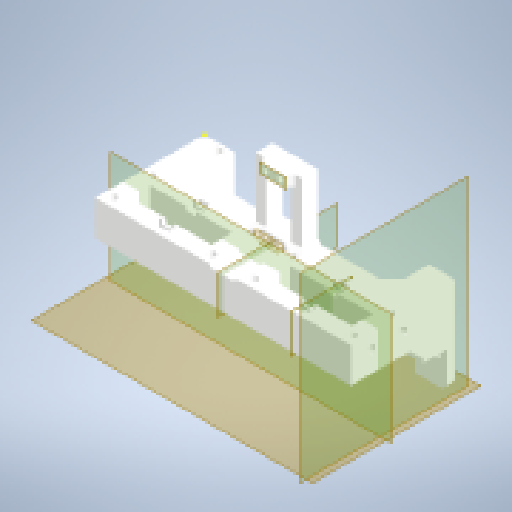
# Autodesk Inventor part: крепление ушей
Saved by Autodesk Inventor 2024.2 (Build 282272000, 272)
## iProperties
Created: 2026-10-17
Part Number: крепление ушей
Material: PLA
Document SubType Name: Modeling
Designer: katya_notebook
Density: 1.24 g/cm^3
Appearance: Типовые
Author: katya_notebook
Autodesk Inventor part; units mm, degrees
ref_plane "РабПлоскость1" through (124, 0, 0) normal (-1, 0, 0) x (0, 0, 1)
sketch "Эскиз1" plane through (124, 0, 0) normal (-1, 0, 0) x (0, 0, 1)
  line L0 (26, 41.5014) -> (53, 41.5014)
  line L1 (53, 41.5014) -> (53, 24.5014)
  line L2 (53, 24.5014) -> (26, 24.5014)
  line L3 (26, 24.5014) -> (26, 41.5014)
  line L4 (4.9014, 14.5719) -> (64.9014, 14.5719) projected
  line L5 (42.1269, 20.5014) -> (32.0731, 20.5014) projected
  point P0 (0, 0)
  dimension "d1" = 27
  dimension "d3" = 17
  dimension "d4" = 4
  dimension "d11" = 26
  constraints: 8 end point, 2 parallel, 1 horizontal, 1 perpendicular
  measures "d1" distance between parallel lines of L3 L1
  measures "d3" distance of L2.end L0.start
  measures "d4" distance between parallel lines of L2 L5
  measures "d11" distance from line of L3 point (0, 0)
ref_plane "РабПлоскость2" through (0, -1.6936, -1.831) normal (1, 0, 0) x (0, 1, 0)
ref_plane "РабПлоскость5" through (0, -2.5349, -1.831) normal (1, 0, 0) x (0, 1, 0)
extrude "Выдавливание1" add sketch "Эскиз1" along normal up to surface (124 mm away)
ref_plane "РабПлоскость3" through (124, 24.5014, 39.5) normal (0, 0, -1) x (-1, 0, 0)
sketch "Эскиз4" plane through (124, 41.5014, 53) normal (0, 1, 0) x (1, 0, 0)
  line L0 (-7.9, 8.5) -> (-47.9, 8.5)
  line L1 (-47.9, 8.5) -> (-47.9, 18.5)
  line L2 (-47.9, 18.5) -> (-7.9, 18.5)
  line L3 (-7.9, 18.5) -> (-7.9, 8.5)
  line L4 (-148.8, 13.5) -> (24.8, 13.5) projected
  line L5 (0, 0) -> (0, 27) projected
  line L6 (0, 0) -> (-124, 0) projected
  line L7 (-62, 0) -> (-62, 27)
  line L8 (0, 27) -> (-124, 27) projected
  line L9 (-116.1, 8.5) -> (-76.1, 8.5)
  line L10 (-76.1, 8.5) -> (-76.1, 18.5)
  line L11 (-76.1, 18.5) -> (-116.1, 18.5)
  line L12 (-116.1, 18.5) -> (-116.1, 8.5)
  point P0 (-124, 53)
  point P1 (-27.9, 18.5)
  point P2 (-96.1, 18.5)
  dimension "d16" = 5
  dimension "d17" = 5
  dimension "d18" = 27.9
  dimension "d19" = 40
  dimension "d38" = 62
  constraints: 18 end point, 5 symmetric about line, 3 midpoint, 2 parallel, 1 horizontal, 1 perpendicular, 1 vertical
  measures "d16" distance from line of L4 point (-27.9, 18.5)
  measures "d17" distance between parallel lines of L4 L0
  measures "d18" distance from line of point (-27.9, 18.5) L5
  measures "d19" distance between parallel lines of L3 L1
  measures "d38" distance between parallel lines of L5 L7
extrude "Выдавливание4" cut sketch "Эскиз4" against normal blind 37.75 contours L0 L1 L4 L3 | L4 L1 L2 L3 | L12 L11 L10 L4 | L4 L10 L9 L12
ref_plane "РабПлоскость4" through (96.1, 41.5014, 34.5) normal (-1, 0, 0) x (0, 0, 1)
sketch "Эскиз6" plane through (124, 41.5014, 53) normal (0, 1, 0) x (1, 0, 0)
  line L0 (-30.6025, 11) -> (-25.6025, 11) projected
  line L1 (-30.6025, 11) -> (-25.6025, 11)
  line L2 (-25.6025, 11) -> (-25.6025, 2.1524)
  line L3 (-25.6025, 2.1524) -> (-30.6025, 2.1524)
  line L4 (-30.6025, 2.1524) -> (-30.6025, 11)
  line L5 (-31.9975, 7) -> (-24.2075, 7)
  line L6 (-24.2075, 7) -> (-24.2075, 3.75)
  line L7 (-24.2075, 3.75) -> (-31.9975, 3.75)
  line L8 (-31.9975, 3.75) -> (-31.9975, 7)
  line L9 (-28.1025, 3.75) -> (-28.1025, 7)
  line L10 (-28.1025, 11) -> (-28.1025, 2.1524)
  line L11 (-7.9, 8.5) -> (-47.9, 8.5) projected
  line L12 (-47.9, 8.5) -> (-47.9, 18.5) projected
  line L13 (-47.9, 13.5) -> (-7.9, 13.5)
  line L14 (-25.6025, 16) -> (-25.6025, 24.8476)
  line L15 (-25.6025, 24.8476) -> (-30.6025, 24.8476)
  line L16 (-30.6025, 24.8476) -> (-30.6025, 16)
  line L17 (-31.9975, 20) -> (-24.2075, 20)
  line L18 (-24.2075, 20) -> (-24.2075, 23.25)
  line L19 (-24.2075, 23.25) -> (-31.9975, 23.25)
  line L20 (-31.9975, 23.25) -> (-31.9975, 20)
  line L21 (-28.1025, 23.25) -> (-28.1025, 20)
  line L22 (-28.1025, 16) -> (-28.1025, 24.8476)
  line L23 (-7.9, 18.5) -> (-47.9, 18.5)
  line L24 (0, 0) -> (-124, 0) projected
  line L25 (-62, 0) -> (-62, 27)
  line L26 (0, 27) -> (-124, 27) projected
  line L27 (-93.3975, 11) -> (-98.3975, 11)
  line L28 (-93.3975, 11) -> (-98.3975, 11)
  line L29 (-98.3975, 11) -> (-98.3975, 2.1524)
  line L30 (-98.3975, 2.1524) -> (-93.3975, 2.1524)
  line L31 (-93.3975, 2.1524) -> (-93.3975, 11)
  line L32 (-92.0025, 7) -> (-99.7925, 7)
  line L33 (-99.7925, 7) -> (-99.7925, 3.75)
  line L34 (-99.7925, 3.75) -> (-92.0025, 3.75)
  line L35 (-92.0025, 3.75) -> (-92.0025, 7)
  line L36 (-95.8975, 3.75) -> (-95.8975, 7)
  line L37 (-95.8975, 11) -> (-95.8975, 2.1524)
  line L38 (-95.8975, 16) -> (-95.8975, 24.8476)
  line L39 (-95.8975, 23.25) -> (-95.8975, 20)
  line L40 (-93.3975, 24.8476) -> (-93.3975, 16)
  line L41 (-92.0025, 23.25) -> (-92.0025, 20)
  line L42 (-98.3975, 16) -> (-98.3975, 24.8476)
  line L43 (-98.3975, 24.8476) -> (-93.3975, 24.8476)
  line L44 (-99.7925, 20) -> (-99.7925, 23.25)
  line L45 (-92.0025, 20) -> (-99.7925, 20)
  line L46 (-99.7925, 23.25) -> (-92.0025, 23.25)
  point P0 (-124, 53)
  point P1 (-24.2075, 5.375)
  point P2 (-28.1025, 5.375)
  point P3 (-24.2075, 21.625)
  point P4 (-28.1025, 21.625)
  point P5 (-99.7925, 5.375)
  point P6 (-95.8975, 5.375)
  point P7 (-95.8975, 21.625)
  point P8 (-99.7925, 21.625)
  dimension "d24" = 0
  dimension "d25" = 3.25
  dimension "d26" = 7.79
  dimension "d27" = 3.895
  dimension "d28" = 0
  dimension "d29" = 1.5
  constraints: 84 end point, 44 symmetric about line, 15 midpoint, 4 parallel, 3 horizontal, 3 perpendicular
  measures "d24" distance from line of L2 L0.end
  measures "d25" distance of L5.end L6.end
  measures "d26" distance of L5.start L5.end
  measures "d27" distance of point (-24.207, 5.375) point (-28.102, 5.375)
  measures "d28" distance between parallel lines of L10 L9
  measures "d29" distance between parallel lines of L11 L5
extrude "Выдавливание5" cut sketch "Эскиз6" against normal blind 3.5 contours L5 L9 L7 L4 | L4 L7 L8 L5 | L5 L2 L7 L9 | L5 L6 L7 L2 | L17 L21 L19 L14 | L14 L19 L18 L17 | L17 L16 L19 L21 | L17 L20 L19 L16 | L32 L35 L34 L31 | L31 L34 L36 L32 | L36 L34 L29 L32 | L29 L34 L33 L32 | L46 L40 L45 L38 | L38 L45 L42 L46 | L42 L45 L44 L46 | L46 L41 L45 L40
sketch "Эскиз7" plane through (124, 41.5014, 53) normal (0, 1, 0) x (1, 0, 0)
  line L0 (-30.6025, 2.1524) -> (-25.6025, 2.1524)
  line L1 (-25.6025, 2.1524) -> (-25.6025, 24.8476)
  line L2 (-25.6025, 24.8476) -> (-30.6025, 24.8476)
  line L3 (-30.6025, 24.8476) -> (-30.6025, 2.1524)
  line L4 (0, 27) -> (-124, 27) projected
  line L5 (-62, 27) -> (-62, 0)
  line L6 (0, 0) -> (-124, 0) projected
  line L7 (-93.3975, 2.1524) -> (-98.3975, 2.1524)
  line L8 (-98.3975, 2.1524) -> (-98.3975, 24.8476)
  line L9 (-98.3975, 24.8476) -> (-93.3975, 24.8476)
  line L10 (-93.3975, 24.8476) -> (-93.3975, 2.1524)
  point P0 (-124, 53)
  constraints: 18 end point, 6 symmetric about line, 4 coincident, 2 midpoint, 2 parallel, 1 horizontal, 1 perpendicular
extrude "Выдавливание6" cut sketch "Эскиз7" against normal blind 2
sketch "Эскиз8" plane through (124, 41.5014, 53) normal (0, 1, 0) x (1, 0, 0)
  line L0 (-30.6025, 2.1524) -> (-30.6025, 3.75) projected
  line L1 (-30.6025, 3.75) -> (-31.9975, 3.75) projected
  line L2 (-31.9975, 3.75) -> (-31.9975, 7) projected
  line L3 (-31.9975, 7) -> (-30.6025, 7) projected
  line L4 (-30.6025, 7) -> (-30.6025, 8.5) projected
  line L5 (-30.6025, 8.5) -> (-47.9, 8.5) projected
  line L6 (-47.9, 8.5) -> (-47.9, 18.5) projected
  line L7 (-47.9, 18.5) -> (-30.6025, 18.5) projected
  line L8 (-30.6025, 18.5) -> (-30.6025, 20) projected
  line L9 (-30.6025, 20) -> (-31.9975, 20) projected
  line L10 (-31.9975, 20) -> (-31.9975, 23.25) projected
  line L11 (-31.9975, 23.25) -> (-30.6025, 23.25) projected
  line L12 (-30.6025, 23.25) -> (-30.6025, 24.8476) projected
  line L13 (-30.6025, 24.8476) -> (-25.6025, 24.8476) projected
  line L14 (-25.6025, 24.8476) -> (-25.6025, 23.25) projected
  line L15 (-25.6025, 23.25) -> (-24.2075, 23.25) projected
  line L16 (-24.2075, 23.25) -> (-24.2075, 20) projected
  line L17 (-24.2075, 20) -> (-25.6025, 20) projected
  line L18 (-25.6025, 20) -> (-25.6025, 18.5) projected
  line L19 (-25.6025, 18.5) -> (-7.9, 18.5) projected
  line L20 (-7.9, 18.5) -> (-7.9, 8.5) projected
  line L21 (-7.9, 8.5) -> (-25.6025, 8.5) projected
  line L22 (-25.6025, 8.5) -> (-25.6025, 7) projected
  line L23 (-25.6025, 7) -> (-24.2075, 7) projected
  line L24 (-24.2075, 7) -> (-24.2075, 3.75) projected
  line L25 (-24.2075, 3.75) -> (-25.6025, 3.75) projected
  line L26 (-25.6025, 3.75) -> (-25.6025, 2.1524) projected
  line L27 (-25.6025, 2.1524) -> (-30.6025, 2.1524) projected
  line L28 (0, 0) -> (0, 27) projected
  line L29 (0, 27) -> (-124, 27) projected
  line L30 (0, 0) -> (-124, 0) projected
  line L31 (-55.8, 0) -> (-47.9, 8.5)
  line L32 (-47.9, 18.5) -> (-55.8, 27)
  line L33 (0, 0) -> (-7.9, 8.5)
  line L34 (-7.9, 18.5) -> (0, 27)
  circle A0 centre (-51.85, 4.25) radius 2.1
  circle A1 centre (-51.85, 22.75) radius 2.1
  circle A2 centre (-3.95, 4.25) radius 2.1
  circle A3 centre (-3.95, 22.75) radius 2.1
  line L35 (-124, 0) -> (-124, 27) projected
  line L36 (0, 27) -> (-124, 27) projected
  line L37 (-62, 27) -> (-62, 0)
  line L38 (-93.3975, 2.1524) -> (-93.3975, 3.75)
  line L39 (-93.3975, 3.75) -> (-92.0025, 3.75)
  line L40 (-92.0025, 3.75) -> (-92.0025, 7)
  line L41 (-92.0025, 7) -> (-93.3975, 7)
  line L42 (-93.3975, 7) -> (-93.3975, 8.5)
  line L43 (-93.3975, 8.5) -> (-76.1, 8.5)
  line L44 (-76.1, 8.5) -> (-76.1, 18.5)
  line L45 (-76.1, 18.5) -> (-93.3975, 18.5)
  line L46 (-93.3975, 18.5) -> (-93.3975, 20)
  line L47 (-93.3975, 20) -> (-92.0025, 20)
  line L48 (-92.0025, 20) -> (-92.0025, 23.25)
  line L49 (-92.0025, 23.25) -> (-93.3975, 23.25)
  line L50 (-93.3975, 23.25) -> (-93.3975, 24.8476)
  line L51 (-93.3975, 24.8476) -> (-98.3975, 24.8476)
  line L52 (-98.3975, 24.8476) -> (-98.3975, 23.25)
  line L53 (-98.3975, 23.25) -> (-99.7925, 23.25)
  line L54 (-99.7925, 23.25) -> (-99.7925, 20)
  line L55 (-99.7925, 20) -> (-98.3975, 20)
  line L56 (-98.3975, 20) -> (-98.3975, 18.5)
  line L57 (-98.3975, 18.5) -> (-116.1, 18.5)
  line L58 (-116.1, 18.5) -> (-116.1, 8.5)
  line L59 (-116.1, 8.5) -> (-98.3975, 8.5)
  line L60 (-98.3975, 8.5) -> (-98.3975, 7)
  line L61 (-98.3975, 7) -> (-99.7925, 7)
  line L62 (-99.7925, 7) -> (-99.7925, 3.75)
  line L63 (-99.7925, 3.75) -> (-98.3975, 3.75)
  line L64 (-98.3975, 3.75) -> (-98.3975, 2.1524)
  line L65 (-98.3975, 2.1524) -> (-93.3975, 2.1524)
  line L66 (-76.1, 18.5) -> (-68.2, 27)
  circle A4 centre (-72.15, 4.25) radius 2.1
  circle A5 centre (-72.15, 22.75) radius 2.1
  circle A6 centre (-120.05, 4.25) radius 2.1
  circle A7 centre (-120.05, 22.75) radius 2.1
  point P0 (-124, 53)
  dimension "d35" = 4.2
  constraints: 68 end point, 33 symmetric about line, 8 centre point, 6 midpoint, 3 equal radius, 2 parallel, 4 other
  measures "d35" diameter of A0
extrude "Выдавливание7" cut sketch "Эскиз8" against normal blind 5 contours A0 L31 | L31 A0 | A1 L32 | L32 A1 | A2 L33 | L33 A2 | A3 L34 | L34 A3 | A5 L66 | L66 A5 | A4 | A6 | A7
sketch "Эскиз9" plane through (124, 41.5014, 53) normal (0, 1, 0) x (1, 0, 0)
  point P0 (-124, 53)
ref_plane "РабПлоскость6" through (62, 24.5014, 26) normal (-1, 0, 0) x (0, 0, 1)
sketch "Эскиз10" plane through (124, 24.5014, 53) normal (0, 0, 1) x (1, 0, 0)
  line L0 (-56, 20) -> (-68, 20) projected
  line L1 (-68, 20) -> (-68, 16.5) projected
  arc A0 (-68, 16.5) -> (-67, 15.5) centre (-67, 16.5) ccw projected
  line L2 (-67, 15.5) -> (-63.25, 15.5) projected
  line L3 (-63.25, 15.5) -> (-63.25, 17.5) projected
  arc A1 (-61.9814, 18.698) -> (-63.25, 17.5) centre (-62.05, 17.5) ccw projected
  line L4 (-61.9814, 18.698) -> (-61.8814, 18.698) projected
  arc A2 (-60.6128, 17.5) -> (-61.8814, 18.698) centre (-61.8128, 17.5) ccw projected
  line L5 (-60.6128, 17.5) -> (-60.6128, 15.5) projected
  line L6 (-60.6128, 15.5) -> (-57, 15.5) projected
  arc A3 (-57, 15.5) -> (-56, 16.5) centre (-57, 16.5) ccw projected
  line L7 (-56, 16.5) -> (-56, 20) projected
  circle A4 centre (-58.5, 17.75) radius 1.25 projected
  circle A5 centre (-65.5, 17.75) radius 1.25 projected
  line L8 (-63.25, 15.5) -> (-60.6128, 15.5)
  point P0 (-124, -24.5014)
  constraints: 2 end point, 1 horizontal
extrude "Выдавливание8" cut sketch "Эскиз10" against normal blind 40 contours L7 A3 L6 L5 A2 L4 A1 L3 L2 A0 L1 L0 | L8 L3 A1 L4 A2 L5 | A4 | A5
sketch "Эскиз11" plane through (124, 24.5014, 26) normal (0, 0, -1) x (-1, 0, 0)
  line L0 (68, 20) -> (56, 20) projected
  line L1 (56, 16.5) -> (56, 20) projected
  arc A0 (56, 16.5) -> (57, 15.5) centre (57, 16.5) ccw projected
  line L2 (60.6128, 15.5) -> (57, 15.5) projected
  line L3 (60.6128, 17.5) -> (60.6128, 15.5) projected
  arc A1 (61.8814, 18.698) -> (60.6128, 17.5) centre (61.8128, 17.5) ccw projected
  line L4 (61.9814, 18.698) -> (61.8814, 18.698) projected
  arc A2 (63.25, 17.5) -> (61.9814, 18.698) centre (62.05, 17.5) ccw projected
  line L5 (63.25, 15.5) -> (63.25, 17.5) projected
  line L6 (67, 15.5) -> (63.25, 15.5) projected
  arc A3 (67, 15.5) -> (68, 16.5) centre (67, 16.5) ccw projected
  line L7 (68, 20) -> (68, 16.5) projected
  circle A4 centre (58.5, 17.75) radius 1.25 projected
  circle A5 centre (65.5, 17.75) radius 1.25 projected
  line L8 (60.6128, 15.5) -> (63.25, 15.5)
  line L9 (67, 15.5) -> (57, 15.5) projected
  point P0 (124, -24.5014)
  constraints: 2 end point, 1 collinear
ref_plane "РабПлоскость7" through (55.9896, 40.002, 28.85) normal (0, 0, -1) x (0, 1, 0)
extrude "Выдавливание9" add sketch "Эскиз11" against normal up to surface (2.85 mm away)
ref_plane "РабПлоскость9" through (62, 56.0297, 30.5) normal (0, 0, 1) x (0, -1, 0)
sketch "Эскиз14" plane through (124, 24.5014, 26) normal (0, 0, -1) x (-1, 0, 0)
  circle A0 centre (65.5, 17.75) radius 1.25 projected
  circle A1 centre (58.5, 17.75) radius 1.25 projected
  line L0 (0, 17) -> (56, 17) projected
  line L1 (0, 17) -> (0, 0) projected
  line L2 (0, 0) -> (124, 0) projected
  line L3 (124, 17) -> (124, 0) projected
  line L4 (68, 17) -> (124, 17) projected
  line L5 (68, 17) -> (68, 20) projected
  line L6 (68, 20) -> (56, 20) projected
  line L7 (56, 20) -> (56, 17) projected
  point P0 (124, -24.5014)
extrude "Выдавливание11" add sketch "Эскиз14" along normal blind 8
sketch "Эскиз15" plane through (68, 41.5014, 53) normal (0, 1, 0) x (1, 0, 0)
  line L0 (0, 46) -> (0, 24.15) projected
  line L1 (0, 35) -> (56, 35) projected
  line L2 (0, 35) -> (5, 35)
  line L3 (5, 35) -> (5, 27)
  line L4 (5, 27) -> (0, 27)
  line L5 (0, 27) -> (0, 35)
  line L6 (56, 0) -> (-68, 0) projected
  line L7 (-6, 0) -> (-6, 35)
  line L8 (56, 35) -> (-68, 35) projected
  line L9 (-12, 46) -> (-12, 24.15)
  line L10 (-12, 35) -> (-68, 35)
  line L11 (-12, 35) -> (-17, 35)
  line L12 (-17, 35) -> (-17, 27)
  line L13 (-17, 27) -> (-12, 27)
  line L14 (-12, 27) -> (-12, 35)
  line L15 (-68, 35) -> (56, 35)
  point P0 (-68, 53)
  point P1 (0, 27)
  point P2 (5, 35)
  point P3 (-12, 27)
  point P4 (-12, 35)
  point P5 (-17, 35)
  dimension "d48" = 8
  dimension "d49" = 5
  constraints: 24 end point, 8 symmetric about line, 2 midpoint, 2 parallel, 1 horizontal, 1 perpendicular
  measures "d48" distance of L2.end L3.end
  measures "d49" distance of L3.end L4.end
extrude "Выдавливание12" add sketch "Эскиз15" along normal blind 31
ref_plane "РабПлоскость10" through (62, 56.0297, 28.85) normal (0, 0, -1) x (0, 1, 0)
sketch "Эскиз16" plane through (62, 56.0297, 28.85) normal (0, 0, -1) x (0, 1, 0)
  line L0 (11.4717, 6) -> (11.4717, -6) projected
  line L1 (14.9717, -6) -> (11.4717, -6) projected
  arc A0 (14.9717, -6) -> (15.9717, -5) centre (14.9717, -5) ccw projected
  line L2 (15.9717, -1.25) -> (15.9717, -5) projected
  line L3 (13.9717, -1.25) -> (15.9717, -1.25) projected
  arc A1 (12.7717, -0.05) -> (13.9717, -1.25) centre (13.9717, -0.05) ccw projected
  line L4 (12.7717, 0.05) -> (12.7717, -0.05) projected
  arc A2 (13.9717, 1.25) -> (12.7717, 0.05) centre (13.9717, 0.05) ccw projected
  line L5 (15.9717, 1.25) -> (13.9717, 1.25) projected
  line L6 (15.9717, 5) -> (15.9717, 1.25) projected
  arc A3 (15.9717, 5) -> (14.9717, 6) centre (14.9717, 5) ccw projected
  line L7 (11.4717, 6) -> (14.9717, 6) projected
  circle A4 centre (13.7217, 3.5) radius 1.25 projected
  circle A5 centre (13.7217, -3.5) radius 1.25 projected
  line L8 (15.9717, 1.9965) -> (15.9717, -3.5)
  line L9 (15.9717, -4.8481) -> (14.2694, -4.8481)
  line L10 (14.2694, -4.8481) -> (14.2694, -6)
  line L11 (14.2694, -6) -> (15.9717, -6)
  line L12 (15.9717, -6) -> (15.9717, -4.8481)
  line L13 (15.9717, 5) -> (13.9717, 5)
  line L14 (13.9717, 5) -> (13.9717, 6)
  line L15 (13.9717, 6) -> (15.9717, 6)
  line L16 (15.9717, 6) -> (15.9717, 5)
  line L17 (16.4717, 11) -> (16.4717, 6) projected
  line L18 (16.4717, 6) -> (15.9717, 6)
  line L19 (15.9717, 6) -> (15.9717, -6)
  line L20 (15.9717, -6) -> (16.4717, -6)
  line L21 (16.4717, -6) -> (16.4717, 6)
  point P0 (-56.0297, -62)
  point P1 (15.9717, 6)
  constraints: 26 end point, 6 parallel, 5 point on line, 3 horizontal, 3 perpendicular
extrude "Выдавливание13" add sketch "Эскиз16" along normal up to surface (10.85 mm away)
chamfer "Фаска1" distance 2 angle 45 8 edges at (56, 41.5014, 27.425) (53.5, 41.5014, 26) (51, 41.5014, 22) (68, 41.5014, 27.425) (70.5, 41.5014, 26) (73, 41.5014, 22) (68, 70.0014, 26) (56, 70.0014, 26)
sketch "Эскиз17" plane through (0, 24.5014, 53) normal (-1, 0, 0) x (0, 0, 1)
  circle A0 centre (-25, 7.5) radius 2.1
  circle A1 centre (-10, 7.5) radius 2.1
  line L0 (0, 0) -> (0, 17) projected
  line L1 (-35, 0) -> (-35, 17) projected
  line L2 (-35, 0) -> (0, 0) projected
  point P0 (-53, -24.5014)
  dimension "d57" = 4.2
  dimension "d58" = 10
  dimension "d59" = 10
  dimension "d60" = 7.5
  constraints: 2 centre point, 1 equal radius, 1 horizontal alignment
  measures "d57" diameter of A1
  measures "d58" distance from line of L0 A1.centre
  measures "d59" distance from line of L1 A0.centre
  measures "d60" distance from line of A0.centre L2
extrude "Выдавливание14" cut sketch "Эскиз17" against normal blind 4
sketch "Эскиз18" plane through (124, 0, 0) normal (1, 0, 0) x (0, 0, -1)
  circle A0 centre (-43, 34.5014) radius 2
  circle A1 centre (-28, 34.5014) radius 2
  line L0 (-18, 24.5014) -> (-53, 24.5014) projected
  line L1 (-53, 24.5014) -> (-53, 41.5014) projected
  line L2 (-18, 41.5014) -> (-18, 24.5014) projected
  point P0 (0, 0)
  dimension "d63" = 4
  dimension "d64" = -10
  dimension "d65" = 10
  dimension "d66" = 10
  constraints: 2 centre point, 1 equal radius, 1 horizontal alignment
  measures "d63" diameter of A0
  measures "d64" distance from line of L0 A0.centre
  measures "d65" distance from line of L1 A0.centre
  measures "d66" distance from line of L2 A1.centre
extrude "Выдавливание15" cut sketch "Эскиз18" against normal blind 4
ref_plane "РабПлоскость11" through (62, -0.8413, 37) normal (0, 1, 0) x (1, 0, 0)
sketch "Эскиз19" plane through (62, -0.8413, 37) normal (0, 1, 0) x (1, 0, 0)
  line L0 (-62, 37) -> (-62, -37) projected
  line L1 (62, 37) -> (-62, 37) projected
  circle A0 centre (-52.1785, 33.2118) radius 2.1 projected
  line L2 (-62, 19) -> (-13, 19) projected
  line L3 (-62, 19) -> (-47, 19)
  line L4 (-47, 19) -> (-47, 37)
  line L5 (-47, 37) -> (-62, 37)
  line L6 (-62, 37) -> (-62, 19)
  point P0 (-47, 19)
  dimension "d69" = 15
  constraints: 8 end point, 2 parallel, 1 horizontal, 1 perpendicular, 1 point on line
  measures "d69" distance between parallel lines of L0 L4
extrude "Выдавливание16" add sketch "Эскиз19" along normal up to surface (42.3426 mm away)
ref_plane "РабПлоскость12" through (62, -0.8413, 37) normal (0, 1, 0) x (1, 0, 0)
sketch "Эскиз20" plane through (62, -0.8413, 37) normal (0, 1, 0) x (1, 0, 0)
  line L0 (62, -37) -> (62, 37) projected
  line L1 (62, 37) -> (-62, 37) projected
  line L2 (62, 37) -> (47, 37)
  line L3 (47, 37) -> (47, 30.2636)
  line L4 (47, 30.2636) -> (62, 30.2636)
  line L5 (62, 30.2636) -> (62, 37)
  point P0 (62, 30.2636)
  point P1 (47, 37)
  dimension "d72" = 15
  constraints: 8 end point, 2 parallel, 1 horizontal, 1 perpendicular
  measures "d72" distance of L3.end L4.end
extrude "Выдавливание17" add sketch "Эскиз20" along normal blind 12
sketch "Эскиз21" plane through (62, 11.1587, 37) normal (0, 1, 0) x (1, 0, 0)
  line L0 (62, 30.2636) -> (62, 37) projected
  line L1 (62, 37) -> (47, 37) projected
  line L2 (47, 37) -> (47, 30.2636) projected
  line L3 (47, 30.2636) -> (62, 30.2636) projected
  line L4 (59.143, 30.2636) -> (47, 30.2636)
  line L5 (47, 30.2636) -> (47, 33.6318)
  line L6 (47, 33.6318) -> (59.143, 33.6318)
  line L7 (59.143, 33.6318) -> (59.143, 30.2636)
  line L8 (57.61, -27.9014) -> (57.61, 32.0986) projected
  line L9 (57.61, 32.0986) -> (-12.39, 32.0986) projected
  point P0 (-62, 37)
  dimension "d75" = 1.533
  constraints: 8 end point, 2 parallel, 1 horizontal, 1 midpoint, 1 perpendicular, 1 point on line
  measures "d75" distance between parallel lines of L7 L8
extrude "Выдавливание18" add sketch "Эскиз21" along normal blind 5.343 contours L3 L7 L6 L2 L1 L0
sketch "Эскиз22" plane through (62, 16.5017, 37) normal (0, 1, 0) x (1, 0, 0)
  line L0 (62, 37) -> (62, 11) projected
  line L1 (-62, 37) -> (62, 37) projected
  line L2 (62, 37) -> (47, 37)
  line L3 (47, 37) -> (47, 18.9525)
  line L4 (47, 18.9525) -> (62, 18.9525)
  line L5 (62, 18.9525) -> (62, 37)
  line L6 (47, 33.6318) -> (47, 30.2636) projected
  point P0 (47, 37)
  dimension "d78" = 0
  constraints: 8 end point, 2 parallel, 1 horizontal, 1 perpendicular
  measures "d78" distance between parallel lines of L3 L6
extrude "Выдавливание19" add sketch "Эскиз22" along normal up to surface (24.9996 mm away)
chamfer "Фаска2" distance 6 angle 45 4 edges at (109, 33.0014, 18) (15, 33.0014, 18) (116.5, 24.5014, 18.0475) (7.5, 24.5014, 18)
fillet "Сопряжение1" radius 4 2 edges at (0, 20.33, 0) (124, 20.33, 0)
chamfer "Фаска3" distance 2 angle 45 6 edges at (124, -0.8413, 5.3682) (122.8284, -0.8413, 1.1716) (114.5, -0.8413, 0) (0, -0.8413, 11) (1.1716, -0.8413, 1.1716) (9.5, -0.8413, 0)
